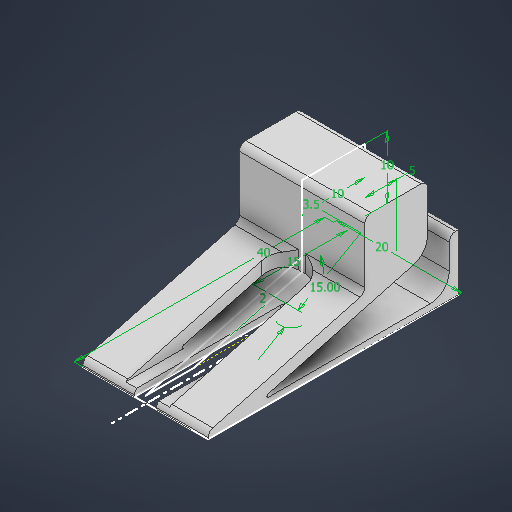
# Autodesk Inventor part: button
Saved by Autodesk Inventor 2027 (Build 310192060, 192F)
## iProperties
Created: 2026-10-20
Part Number: button
Material: Generic
Document SubType Name: Modeling
Designer: Pablo
Density: 1 g/cm^3
Appearance: Default
Author: Pablo
Autodesk Inventor part; units mm, degrees
ref_plane "YZ Plane" through (0, 0, 0) normal (1, 0, 0) x (0, 1, 0)
ref_plane "XZ Plane" through (0, 0, 0) normal (0, 1, 0) x (-1, 0, 0)
ref_plane "XY Plane" through (0, 0, 0) normal (0, 0, 1) x (1, 0, 0)
sketch "Sketch1" plane through (0, 0, 0) normal (0, 1, 0) x (-1, 0, 0)
  line L0 (-10, 20) -> (10, 20)
  line L1 (10, 20) -> (10, -20)
  line L2 (10, -20) -> (-10, -20)
  line L3 (-10, -20) -> (-10, 20)
  line L4 (-10, 20) -> (10, -20) construction
  line L5 (10, 20) -> (-10, -20) construction
  line L6 (0, -25.5253) -> (0, 25.5253)
  arc A0 (-1.75, -3.25) -> (1.75, -3.25) centre (0, -3.25) ccw
  line L7 (1.75, 20) -> (1.75, -3.25)
  line L8 (-1.75, 20) -> (-1.75, -3.25)
  point P0 (0, 0)
  point P1 (0, -5)
  dimension "d0" = 40
  dimension "d1" = 20
  dimension "d2" = 3.5
  dimension "d3" = 15
  constraints: 18 end point, 4 parallel, 3 midpoint, 3 point on circle, 3 point on line, 2 tangent, 1 centre point, 1 horizontal, 1 perpendicular, 1 vertical
  measures "d0" distance of L0.end L1.end
  measures "d1" distance of L1.end L2.end
  measures "d2" diameter of A0
  measures "d3" distance from line of L2 point (0, -5)
extrude "Extrusion1" add sketch "Sketch1" along normal blind 1 contours L0 L8 A0 L6 L2 L3 | L6 A0 L7 L0 L1 L2
sketch "Sketch2" plane through (0, 0, 0) normal (1, 0, 0) x (0, 1, 0)
  line L0 (1, 20) -> (1, -20) construction
  line L1 (1, 20) -> (7.6987, -5)
  line L2 (7.6987, -5) -> (18.3077, -5)
  line L3 (18.3077, -5) -> (18.3077, -15)
  line L4 (18.3077, -15) -> (8.3077, -15)
  line L5 (8.3077, -15) -> (1, 12.2726)
  line L6 (1, 12.2726) -> (1, 20)
  line L7 (0, -20) -> (1, -20) projected
  line L8 (7.6987, -5) -> (5.6282, -5)
  point P0 (0, 0)
  dimension "d6" = 15
  dimension "d7" = 2
  dimension "d8" = 10
  dimension "d9" = 5
  dimension "d10" = 10
  constraints: 14 end point, 3 point on line, 2 horizontal, 2 perpendicular, 1 collinear, 1 parallel
  measures "d6" angle of L0 L5
  measures "d7" distance between parallel lines of L1 L5
  measures "d8" distance between parallel lines of L4 L2
  measures "d9" distance between parallel lines of L4 L7
  measures "d10" distance from line of L4.end L3
extrude "Extrusion2" add sketch "Sketch2" along normal mid plane 20
extrude "Extrusion3" cut sketch "Sketch1" along normal through all contours L0 L6 A0 L8 | L0 L7 A0 L6
extrude "Extrusion4" cut sketch "Sketch2" along normal mid plane 7 contours L1 L8 L5 L6
sketch "Sketch3" plane through (0, 1, 0) normal (0, 1, 0) x (1, 0, 0)
  line L0 (-10, 20) -> (-10, -12.2726) construction
  line L1 (10, -12.2726) -> (10, 20) construction
  line L2 (-10, 20) -> (10, 20)
  line L3 (10, 20) -> (10, 18.5)
  line L4 (10, 18.5) -> (-10, 18.5)
  line L5 (-10, 18.5) -> (-10, 20)
  point P0 (0, 0)
  dimension "d17" = 1.5
  constraints: 8 end point, 2 perpendicular, 1 horizontal, 1 point on line
  measures "d17" distance of L1.end L3.end
extrude "Extrusion5" add sketch "Sketch3" along normal blind 8
fillet "Fillet1" radius 0.25 2 edges at (6.75, 1, 12.2726) (-6.75, 1, 12.2726)
fillet "Fillet2" radius 3 4 edges at (0, 1, -18.5) (0, 8.3077, -15) (3.5, 6.6635, -5) (-3.5, 6.6635, -5)
fillet "Fillet3" radius 1 9 edges at (0, 18.3077, -5) (0, 18.3077, -15) (2, 7.6987, -5) (6.75, 7.6987, -5) (-2, 7.6987, -5) (-6.75, 7.6987, -5) (-6.75, 1, 20) (6.75, 1, 20) (0, 9, -18.5)
body "Solid1"
